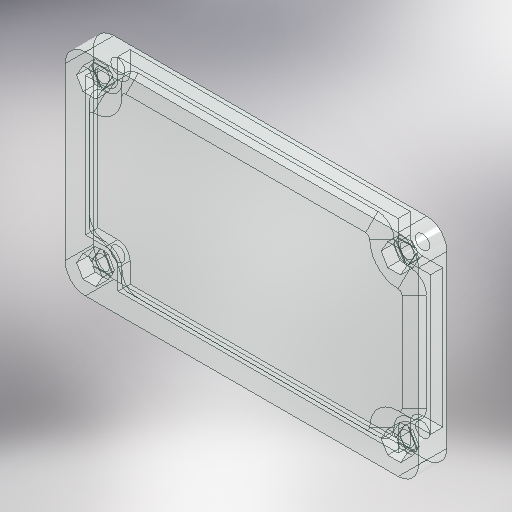
# Autodesk Inventor part: 3D_base_transperanet
Saved by Autodesk Inventor 2025.3 (Build 293356030, 356C)
## iProperties
Created: 2026-02-13
Part Number: 3D_base_transperanet
Material: 一般
Document SubType Name: Modeling
Designer: ibuki_ono
Density: 1 g/cm^3
Appearance: クリア
Author: ibuki_ono
## iProperties of the stored document 3D_base_3D プリント.ipt
Created: 2026-02-13
Part Number: 3D_base_3D プリント
Material: 一般
Document SubType Name: Modeling
Designer: ibuki_ono
Density: 1 g/cm^3
Appearance: 既定
Author: ibuki_ono
Autodesk Inventor part; units mm, degrees
ref_plane "YZ Plane" through (0, 0, 0) normal (1, 0, 0) x (0, 1, 0)
ref_plane "XZ Plane" through (0, 0, 0) normal (0, 1, 0) x (-1, 0, 0)
ref_plane "XY Plane" through (0, 0, 0) normal (0, 0, 1) x (1, 0, 0)
sketch "スケッチ1" plane through (0, 0, 0) normal (0, 0, 1) x (1, 0, 0)
  line L0 (-43.5, -26) -> (43.5, -26)
  line L1 (43.5, -26) -> (43.5, 26)
  line L2 (43.5, 26) -> (-43.5, 26)
  line L3 (-43.5, 26) -> (-43.5, -26)
  line L4 (-43.5, -26) -> (43.5, 26) construction
  line L5 (43.5, -26) -> (-43.5, 26) construction
  point P0 (0, 0)
  dimension "d0" = 87
  dimension "d1" = 52
  constraints: 12 end point, 2 midpoint, 2 parallel, 1 horizontal, 1 perpendicular
  measures "d0" distance of L2.end L1.end
  measures "d1" distance of L1.end L0.end
extrude "押し出し1" add sketch "スケッチ1" along normal blind 4
sketch "スケッチ2" plane through (0, 0, 4) normal (0, 0, 1) x (1, 0, 0)
  line L0 (-37.5, -20) -> (37.5, -20) construction
  line L1 (37.5, -20) -> (37.5, 20) construction
  line L2 (37.5, 20) -> (-37.5, 20) construction
  line L3 (-37.5, 20) -> (-37.5, -20) construction
  line L4 (-37.5, -20) -> (37.5, 20) construction
  line L5 (37.5, -20) -> (-37.5, 20) construction
  point P0 (0, 0)
  point P1 (-37.5, 20)
  dimension "d4" = 75
  dimension "d5" = 40
  constraints: 12 end point, 4 coincident, 2 midpoint, 2 parallel, 1 horizontal, 1 perpendicular
  measures "d4" distance of L2.end L1.end
  measures "d5" distance of L1.end L0.end
hole "穴1" at (-37.5, 20, 4) at (37.5, 20, 4) at (37.5, -20, 4) at (-37.5, -20, 4) direction (0, 0, -1) diameter 3.5 end through all
sketch "スケッチ3" plane through (0, 0, 4) normal (0, 0, 1) x (1, 0, 0)
  circle A0 centre (-37.5, 20) radius 1.75 projected
  line L0 (-40.6754, 20) -> (-39.0877, 22.75)
  line L1 (-39.0877, 22.75) -> (-35.9123, 22.75)
  line L2 (-35.9123, 22.75) -> (-34.3246, 20)
  line L3 (-34.3246, 20) -> (-35.9123, 17.25)
  line L4 (-35.9123, 17.25) -> (-39.0877, 17.25)
  line L5 (-39.0877, 17.25) -> (-40.6754, 20)
  point P0 (0, 0)
  dimension "d13" = 5.5
  constraints: 12 end point, 1 coincident, 1 horizontal alignment, 13 other
  measures "d13" distance between parallel lines of L4 L1
extrude "押し出し2" cut sketch "スケッチ3" against normal blind 3
sketch "スケッチ4" plane through (0, 0, 1) normal (0, 0, 1) x (1, 0, 0)
  line L0 (-35.9123, 17.25) -> (-39.0877, 17.25) projected
  line L1 (-34.3246, 20) -> (-35.9123, 17.25) projected
  line L2 (-35.9123, 22.75) -> (-34.3246, 20) projected
  line L3 (-39.0877, 22.75) -> (-35.9123, 22.75) projected
  line L4 (-40.6754, 20) -> (-39.0877, 22.75) projected
  line L5 (-39.0877, 17.25) -> (-40.6754, 20) projected
  circle A0 centre (-37.5, 20) radius 1.75 projected
  line L6 (-39.6651, 21.75) -> (-35.3349, 21.75)
  line L7 (-34.9019, 21) -> (-37.067, 17.25)
  line L8 (-35.9123, 17.25) -> (-39.0877, 17.25) projected
  line L9 (-37.933, 17.25) -> (-40.0981, 21)
  line L10 (-39.0877, 22.75) -> (-35.9123, 22.75) projected
  line L11 (-34.3246, 20) -> (-35.9123, 17.25) projected
  line L12 (-39.0877, 17.25) -> (-40.6754, 20) projected
  circle A1 centre (-37.5, 20) radius 1.75 projected
  point P0 (0, 0)
  point P1 (-39.0155, 19.125)
  point P2 (-35.9845, 19.125)
  point P3 (-37.5, 21.75)
  constraints: 6 end point, 6 point on line, 3 parallel, 3 tangent, 1 horizontal
extrude "押し出し3" cut sketch "スケッチ4" against normal blind 0.2 contours L0 L9 A0 L7 | A0 L6 L2 L7 | L9 L4 L6 A0
mirror "ミラー1" about plane through (0, 0, 0) normal (0, 1, 0) of "押し出し2", "押し出し3"
mirror "ミラー2" about plane through (0, 0, 0) normal (1, 0, 0) of "押し出し2", "押し出し3", "ミラー1"
sketch "スケッチ5" plane through (0, 0, 0) normal (0, 0, -1) x (-1, 0, 0)
  line L0 (-43.5, 26) -> (43.5, 26) projected
  line L1 (-43.5, -26) -> (-43.5, 26) projected
  line L2 (43.5, -26) -> (-43.5, -26) projected
  line L3 (43.5, 26) -> (43.5, -26) projected
  line L4 (41.5, 24) -> (-41.5, 24)
  line L5 (-41.5, 24) -> (-41.5, -24)
  line L6 (-41.5, -24) -> (41.5, -24)
  line L7 (41.5, -24) -> (41.5, 24)
  line L8 (-43.5, 26) -> (-33.5, 26)
  line L9 (-33.5, 26) -> (-33.5, 16)
  line L10 (-33.5, 16) -> (-43.5, 16)
  line L11 (-43.5, 16) -> (-43.5, 26)
  line L12 (43.5, 26) -> (33.5, 26)
  line L13 (33.5, 26) -> (33.5, 16)
  line L14 (33.5, 16) -> (43.5, 16)
  line L15 (43.5, 16) -> (43.5, 26)
  line L16 (43.5, -26) -> (33.5, -26)
  line L17 (33.5, -26) -> (33.5, -16)
  line L18 (33.5, -16) -> (43.5, -16)
  line L19 (43.5, -16) -> (43.5, -26)
  line L20 (-43.5, -26) -> (-33.5, -26)
  line L21 (-33.5, -26) -> (-33.5, -16)
  line L22 (-33.5, -16) -> (-43.5, -16)
  line L23 (-43.5, -16) -> (-43.5, -26)
  line L24 (-41.5, 0) -> (41.5, 0)
  point P0 (0, 0)
  point P1 (-41.5, -16)
  point P2 (-33.5, -24)
  point P3 (33.5, -24)
  point P4 (41.5, -16)
  dimension "d18" = 2
  dimension "d19" = 10
  dimension "d20" = 10
  dimension "d21" = 10
  dimension "d22" = 10
  dimension "d23" = 10
  dimension "d24" = 10
  dimension "d25" = 10
  dimension "d26" = 10
  constraints: 42 end point, 8 parallel, 4 horizontal, 4 perpendicular, 2 midpoint, 3 other
  measures "d18" distance between parallel lines of L0 L4
  measures "d19" distance of L9.end L10.end
  measures "d20" distance of L8.end L9.end
  measures "d21" distance of L14.end L13.end
  measures "d22" distance of L13.end L12.end
  measures "d23" distance of L17.end L18.end
  measures "d24" distance of L16.end L17.end
  measures "d25" distance of L22.end L21.end
  measures "d26" distance of L21.end L20.end
extrude "押し出し4" cut sketch "スケッチ5" against normal blind 3 contours L5 L24 L7 L18 L17 L6 L21 L22
mirror "ミラー3" about plane through (0, 0, 0) normal (0, 1, 0) of "押し出し4"
fillet "フィレット1" radius 4 12 edges at (33.5, -16, 1.5) (41.5, -16, 1.5) (33.5, -24, 1.5) (33.5, 16, 1.5) (33.5, 24, 1.5) (41.5, 16, 1.5) (-33.5, 24, 1.5) (-33.5, 16, 1.5) (-41.5, 16, 1.5) (-41.5, -16, 1.5) (-33.5, -16, 1.5) (-33.5, -24, 1.5)
chamfer "面取り1" distance 3 angle 45 16 edges at (0, -24, 3) (32.3286, -22.8286, 3) (33.5, -20, 3) (37.5, -16, 3) (40.3286, -14.8286, 3) (41.5, 0, 3) (37.5, 16, 3) (33.5, 20, 3) (0, 24, 3) (-33.5, 20, 3) (-37.5, 16, 3) (-41.5, 0, 3) (-40.3286, -14.8286, 3) (-37.5, -16, 3) (-33.5, -20, 3) (-32.3286, -22.8286, 3)
fillet "フィレット2" radius 5 4 edges at (-43.5, 26, 2) (-43.5, -26, 2) (43.5, 26, 2) (43.5, -26, 2)
sketch "スケッチ7" plane through (0, 0, 0) normal (0, 0, -1) x (-1, 0, 0)
  arc A0 (37.5, -16) -> (33.5, -20) centre (37.5, -20) ccw projected
  arc A1 (29.5, -24) -> (33.5, -20) centre (29.5, -20) ccw projected
  line L0 (29.5, -24) -> (-29.5, -24) projected
  arc A2 (-33.5, -20) -> (-29.5, -24) centre (-29.5, -20) ccw projected
  arc A3 (-33.5, -20) -> (-37.5, -16) centre (-37.5, -20) ccw projected
  arc A4 (-41.5, -12) -> (-37.5, -16) centre (-37.5, -12) ccw projected
  line L1 (-41.5, -12) -> (-41.5, 12) projected
  arc A5 (-37.5, 16) -> (-41.5, 12) centre (-37.5, 12) ccw projected
  arc A6 (-37.5, 16) -> (-33.5, 20) centre (-37.5, 20) ccw projected
  arc A7 (-29.5, 24) -> (-33.5, 20) centre (-29.5, 20) ccw projected
  line L2 (-29.5, 24) -> (29.5, 24) projected
  arc A8 (33.5, 20) -> (29.5, 24) centre (29.5, 20) ccw projected
  arc A9 (33.5, 20) -> (37.5, 16) centre (37.5, 20) ccw projected
  arc A10 (41.5, 12) -> (37.5, 16) centre (37.5, 12) ccw projected
  line L3 (41.5, 12) -> (41.5, -12) projected
  arc A11 (37.5, -16) -> (41.5, -12) centre (37.5, -12) ccw projected
  circle A12 centre (37.5, -20) radius 1.75 projected
  circle A13 centre (-37.5, -20) radius 1.75 projected
  circle A14 centre (-37.5, 20) radius 1.75 projected
  circle A15 centre (37.5, 20) radius 1.75 projected
  arc A16 (-43.5, -21) -> (-38.5, -26) centre (-38.5, -21) ccw projected
  line L4 (38.5, -26) -> (-38.5, -26) projected
  arc A17 (38.5, -26) -> (43.5, -21) centre (38.5, -21) ccw projected
  line L5 (43.5, 21) -> (43.5, -21) projected
  arc A18 (43.5, 21) -> (38.5, 26) centre (38.5, 21) ccw projected
  line L6 (-38.5, 26) -> (38.5, 26) projected
  arc A19 (-38.5, 26) -> (-43.5, 21) centre (-38.5, 21) ccw projected
  line L7 (-43.5, -21) -> (-43.5, 21) projected
  line L8 (29.5, 25) -> (-29.5, 25)
  arc A20 (-29.5, 25) -> (-34.5, 20) centre (-29.5, 20) ccw
  arc A21 (-37.5, 17) -> (-34.5, 20) centre (-37.5, 20) ccw
  arc A22 (-37.5, 17) -> (-42.5, 12) centre (-37.5, 12) ccw
  line L9 (-42.5, 12) -> (-42.5, -12)
  arc A23 (-42.5, -12) -> (-37.5, -17) centre (-37.5, -12) ccw
  arc A24 (-34.5, -20) -> (-37.5, -17) centre (-37.5, -20) ccw
  arc A25 (-34.5, -20) -> (-29.5, -25) centre (-29.5, -20) ccw
  line L10 (-29.5, -25) -> (29.5, -25)
  arc A26 (29.5, -25) -> (34.5, -20) centre (29.5, -20) ccw
  arc A27 (37.5, -17) -> (34.5, -20) centre (37.5, -20) ccw
  arc A28 (37.5, -17) -> (42.5, -12) centre (37.5, -12) ccw
  line L11 (42.5, -12) -> (42.5, 12)
  arc A29 (42.5, 12) -> (37.5, 17) centre (37.5, 12) ccw
  arc A30 (34.5, 20) -> (37.5, 17) centre (37.5, 20) ccw
  arc A31 (34.5, 20) -> (29.5, 25) centre (29.5, 20) ccw
  line L12 (42.5, -25) -> (-42.5, -25)
  line L13 (-42.5, -25) -> (-42.5, 25)
  line L14 (-42.5, 25) -> (42.5, 25)
  line L15 (42.5, 25) -> (42.5, -25)
  line L16 (42.5, -25) -> (-42.5, 25) construction
  line L17 (-42.5, -25) -> (42.5, 25) construction
  line L18 (-42.5, 25) -> (-34.5, 25)
  line L19 (-34.5, 25) -> (-34.5, 17)
  line L20 (-34.5, 17) -> (-42.5, 17)
  line L21 (-42.5, 17) -> (-42.5, 25)
  line L22 (42.5, 25) -> (34.5, 25)
  line L23 (34.5, 25) -> (34.5, 17)
  line L24 (34.5, 17) -> (42.5, 17)
  line L25 (42.5, 17) -> (42.5, 25)
  line L26 (42.5, -25) -> (34.5, -25)
  line L27 (34.5, -25) -> (34.5, -17)
  line L28 (34.5, -17) -> (42.5, -17)
  line L29 (42.5, -17) -> (42.5, -25)
  line L30 (-42.5, -25) -> (-34.5, -25)
  line L31 (-34.5, -25) -> (-34.5, -17)
  line L32 (-34.5, -17) -> (-42.5, -17)
  line L33 (-42.5, -17) -> (-42.5, -25)
  point P0 (0, 0)
  point P1 (-34.5, -20)
  point P2 (34.5, 20)
  point P3 (37.5, -17)
  point P4 (34.5, -20)
  point P5 (-29.5, -25)
  dimension "d37" = 1
  constraints: 52 end point, 24 point on circle, 12 centre point, 10 parallel, 7 tangent, 5 horizontal, 5 perpendicular, 2 collinear, 2 midpoint, 1 point on line, 15 other
  measures "d37" distance between parallel lines of L2 L8
extrude "押し出し6" add sketch "スケッチ7" along normal blind 3 contours L28 L15 A17 L12 L27 A27 | L11 L15 A18 L5 A17 | L12 A17 L4 A16 L10 | A30 L23 L14 A18 L15 L24 | L31 L12 A16 L13 L32 A24 | L8 L14 A19 L6 A18 | L13 A16 L7 A19 L9 | A21 L20 L13 A19 L14 L19
